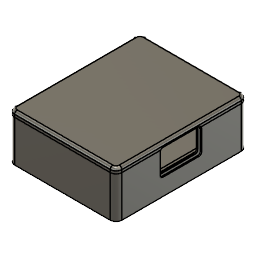
B_involucro_modulo_aquisicao (Autodesk Fusion 360 design; units mm, degrees)
Autodesk Fusion 360 part; units mm, degrees
sketch "Esboço1" plane through (0, 0, 0) normal (0, 0, 1) x (1, 0, 0)
  line L0 (0, 0) -> (38, 0)
  line L1 (0, 0) -> (0, 10)
  line L2 (0, 10) -> (4, 10)
  line L3 (4, 10) -> (4, 8)
  line L4 (4, 8) -> (2, 8)
  line L5 (2, 8) -> (2, 6)
  line L6 (2, 6) -> (4, 6)
  line L7 (4, 6) -> (4, 4)
  line L8 (4, 4) -> (2, 4)
  line L9 (2, 4) -> (2, 2)
  line L10 (2, 2) -> (38, 2)
  line L11 (38, 2) -> (38, 0)
  line L12 (38, 2) -> (38, 0)
  line L13 (38, 2) -> (38, 0)
  line L14 (76, 0) -> (38, 0)
  line L15 (72, 4) -> (74, 4)
  line L16 (74, 2) -> (38, 2)
  line L17 (76, 10) -> (72, 10)
  line L18 (72, 10) -> (72, 8)
  line L19 (74, 4) -> (74, 2)
  line L20 (74, 6) -> (72, 6)
  line L21 (38, 2) -> (38, 0)
  line L22 (72, 6) -> (72, 4)
  line L23 (72, 8) -> (74, 8)
  line L24 (74, 8) -> (74, 6)
  line L25 (76, 0) -> (76, 10)
  point P0 (76, 0)
  dimension "d2" = 10
  dimension "d3" = 4
  dimension "d4" = 2
  dimension "d5" = 2
  dimension "d6" = 2
  dimension "d7" = 2
  dimension "d8" = 2
  dimension "d9" = 2
  dimension "d10" = 2
  dimension "d11" = 36
  constraint coincident L0.start L1.start
  constraint horizontal L0
  constraint perpendicular L0 L1
  constraint perpendicular L1 L2
  constraint perpendicular L2 L3
  constraint perpendicular L1 L4
  constraint perpendicular L4 L5
  constraint perpendicular L5 L6
  constraint perpendicular L6 L7
  constraint perpendicular L7 L8
  constraint perpendicular L0 L9
  constraint perpendicular L9 L10
  constraint symmetric L10.end L11 L12.start
  constraint symmetric L0.end L11 L12.end
  constraint perpendicular L10 L12
  constraint symmetric L0.start L12 L14.start
  constraint symmetric L0.start L12 P0
  constraint symmetric L1.end L12 L17.start
  constraint symmetric L2.end L12 L17.end
  constraint symmetric L3.end L12 L18.end
  constraint symmetric L4.end L12 L23.end
  constraint symmetric L5.end L12 L20.start
  constraint symmetric L6.end L12 L20.end
  constraint symmetric L7.end L12 L15.start
  constraint symmetric L8.end L12 L15.end
  constraint symmetric L9.end L12 L16.start
  constraint symmetric L10.end L12 L11.start
  constraint symmetric L0.end L12 L11.end
  measures "d2" distance of L0.start L1.end
  measures "d3" distance of L1.end L2.end
  measures "d4" distance of L2.end L3.end
  measures "d5" distance of L3.end L4.end
  measures "d6" distance of L4.end L5.end
  measures "d7" distance of L5.end L6.end
  measures "d8" distance of L6.end L7.end
  measures "d9" distance of L7.end L8.end
  measures "d10" distance of L8.end L9.end
  measures "d11" distance of L9.end L10.end
extrude "Extrusão1" add sketch "Esboço1" along normal blind 95 makes body 1
fillet "Arredondamento1" radius 2 1 edges at (0, 10, 47.5) on bodies 1
fillet "Arredondamento1" radius 2 1 edges at (76, 10, 47.5) on bodies 1
sketch "Esboço3" plane through (0, 0, 95) normal (0, 0, 1) x (1, 0, 0)
  line L0 (74, 2) -> (2, 2)
  line L1 (2, 2) -> (2, 4)
  line L2 (2, 4) -> (4, 4)
  line L3 (4, 4) -> (4, 6)
  line L4 (4, 6) -> (2, 6)
  line L5 (2, 6) -> (2, 8)
  line L6 (2, 8) -> (4, 8)
  line L7 (4, 8) -> (4, 10)
  line L8 (4, 10) -> (2, 10)
  arc A0 (2, 10) -> (0, 8) centre (2, 8) ccw
  line L9 (0, 8) -> (0, 0)
  line L10 (0, 0) -> (76, 0)
  line L11 (2, 8) -> (4, 8)
  line L12 (4, 8) -> (4, 6)
  line L13 (4, 6) -> (2, 6)
  line L14 (2, 6) -> (2, 8)
  line L15 (72, 8) -> (74, 8)
  line L16 (74, 8) -> (74, 6)
  line L17 (74, 6) -> (72, 6)
  line L18 (72, 6) -> (72, 8)
  line L19 (76, 0) -> (76, 8)
  line L20 (74, 10) -> (72, 10)
  line L21 (72, 10) -> (72, 8)
  line L22 (72, 8) -> (74, 8)
  line L23 (74, 8) -> (74, 6)
  line L24 (74, 6) -> (72, 6)
  line L25 (72, 6) -> (72, 4)
  line L26 (72, 4) -> (74, 4)
  line L27 (74, 4) -> (74, 2)
  arc A1 (76, 8) -> (74, 10) centre (74, 8) ccw
  constraint horizontal L11
  constraint vertical L12
  constraint horizontal L13
  constraint vertical L14
  constraint coincident L3.end L4.start
  constraint coincident L5.end L6.start
  constraint horizontal L15
  constraint vertical L16
  constraint horizontal L17
  constraint vertical L18
  measures "d143" distance of L9.end
copy_body "Corpo -> Componente1" bodies 1 removing the originals makes body 2 in component "Placa 9x7"
extrude "Extrusão1'" add sketch "Esboço3" against normal blind 2 contours L15 L16 L17 L18 L22 L23 L24 | L4 L5 L6 L11 L12 L13 L14 bodies 2 in component "Placa 9x7"
sketch "Esboço7" plane through (0, 0, 0) normal (0, -1, 0) x (1, 0, 0)
  line L0 (0, 0) -> (76, 0)
  line L1 (76, 95) -> (0, 95)
  line L2 (0, 95) -> (0, 0)
  line L3 (0, 0) -> (0, 47.5)
  line L4 (0, 47.5) -> (38, 47.5)
  line L5 (77, -0.75) -> (-1, -0.75)
  line L6 (-1, -0.75) -> (-1, 95.75)
  line L7 (-1, 95.75) -> (77, 95.75)
  line L8 (77, 95.75) -> (77, -0.75)
  line L9 (77, -0.75) -> (-1, 95.75) construction
  line L10 (-1, -0.75) -> (77, 95.75) construction
  line L11 (75, 97.75) -> (1, 97.75)
  line L12 (-3, 93.75) -> (-3, 1.25)
  line L13 (1, -2.75) -> (75, -2.75)
  line L14 (79, 1.25) -> (79, 93.75)
  line L15 (79, 97.75) -> (-3, -2.75) construction
  line L16 (-3, 97.75) -> (79, -2.75) construction
  arc A0 (1, 97.75) -> (-3, 93.75) centre (1, 93.75) ccw
  arc A1 (79, 93.75) -> (75, 97.75) centre (75, 93.75) ccw
  arc A2 (75, -2.75) -> (79, 1.25) centre (75, 1.25) ccw
  arc A3 (-3, 1.25) -> (1, -2.75) centre (1, 1.25) ccw
  line L17 (76, 0) -> (76, 95)
  point P0 (38, 47.5)
  point P1 (38, 47.5)
  dimension "d45" = 47.5
  dimension "d46" = 38
  dimension "d47" = 96.5
  dimension "d48" = 78
  dimension "d49" = 82
  dimension "d50" = 100.5
  dimension "d54" = 4
  constraint coincident L0.start L2.end
  constraint perpendicular L0 L3
  constraint perpendicular L3 L4
  constraint horizontal L5
  constraint perpendicular L5 L6
  constraint parallel L5 L7
  constraint parallel L6 L8
  constraint coincident L9 P1
  constraint coincident L10 P1
  constraint coincident P1 P0
  constraint horizontal L11
  constraint perpendicular L11 L12
  constraint parallel L11 L13
  constraint parallel L12 L14
  constraint coincident L15 P1
  constraint coincident L16 P1
  constraint coincident L16.start L12
  constraint coincident L16.start L11
  constraint tangent L12 A0
  constraint tangent L11 A0
  constraint coincident L15.start L11
  constraint coincident L15.start L14
  constraint tangent L11 A1
  constraint tangent L14 A1
  constraint equal A0 A1
  constraint coincident L16.end L13
  constraint coincident L16.end L14
  constraint tangent L13 A2
  constraint tangent L14 A2
  constraint equal A0 A2
  constraint coincident L15.end L13
  constraint coincident L15.end L12
  constraint tangent L13 A3
  constraint tangent L12 A3
  constraint equal A0 A3
  measures "d45" distance of L0.start L3.end
  measures "d46" distance of L3.end P1
  measures "d47" distance of L5.end L6.end
  measures "d48" distance of L6.end L7.end
  measures "d49" distance of L15.end L16.end
  measures "d50" distance of L16.start L15.end
  measures "d54" radius of A0
extrude "Extrusão8" add sketch "Esboço7" against normal blind 30 thin wall 1 centred separate body contours L11 L12 L13 L14 A0 A1 A2 A3 makes body 3
copy_body "Corpo -> Componente2" bodies 3 removing the originals makes body 4 in component "Suporte Placa (1)"
extrude "Extrusão1''" add sketch "Esboço7" along normal blind 2 contours L0 L1 L2 L3 L17 | L5 L6 L7 L8 | L11 L12 L13 L14 A0 A1 A2 A3 bodies 4 in component "Suporte Placa (1)"
extrude "Extrusão11" add 1 faces at (51.6667, -2, 62.9167) along direction (0, 1, 0) blind 2 thin wall 0.5 outside on bodies 4 bodies 4 in component "Suporte Placa (1)"
sketch "Esboço1 (2)" plane through (0, 30, 0) normal (0, 1, 0) x (-1, 0, 0) in component "Suporte Placa (1)"
  arc A0 (2.5, 93.75) -> (1.5, 96.1995) centre (-1, 93.75) ccw
  line L0 (2.5, 93.75) -> (2.5, 1.25)
  arc A1 (1.5, -1.1995) -> (2.5, 1.25) centre (-1, 1.25) ccw
  line L1 (1.5, -1.1995) -> (1.5, 96.1995)
  arc A2 (-75, 97.25) -> (-77.4495, 96.25) centre (-75, 93.75) ccw
  line L2 (-75, 97.25) -> (-1, 97.25)
  arc A3 (1.4495, 96.25) -> (-1, 97.25) centre (-1, 93.75) ccw
  line L3 (1.4495, 96.25) -> (-77.4495, 96.25)
  arc A4 (-1, -2.25) -> (1.4495, -1.25) centre (-1, 1.25) ccw
  line L4 (-1, -2.25) -> (-75, -2.25)
  arc A5 (-77.4495, -1.25) -> (-75, -2.25) centre (-75, 1.25) ccw
  line L5 (-77.4495, -1.25) -> (1.4495, -1.25)
  arc A6 (-78.5, 1.25) -> (-77.5, -1.1995) centre (-75, 1.25) ccw
  line L6 (-78.5, 1.25) -> (-78.5, 93.75)
  arc A7 (-77.5, 96.1995) -> (-78.5, 93.75) centre (-75, 93.75) ccw
  line L7 (-77.5, 96.1995) -> (-77.5, -1.1995)
  line L8 (-76.5, 95.25) -> (0.5, 95.25)
  line L9 (0.5, 95.25) -> (0.5, -0.25)
  line L10 (0.5, -0.25) -> (-76.5, -0.25)
  line L11 (-76.5, -0.25) -> (-76.5, 95.25)
  arc A8 (-1, -3.25) -> (3.5, 1.25) centre (-1, 1.25) ccw
  line L12 (3.5, 1.25) -> (3.5, 93.75)
  arc A9 (3.5, 93.75) -> (-1, 98.25) centre (-1, 93.75) ccw
  line L13 (-1, 98.25) -> (-75, 98.25)
  arc A10 (-75, 98.25) -> (-79.5, 93.75) centre (-75, 93.75) ccw
  line L14 (-79.5, 93.75) -> (-79.5, 1.25)
  line L15 (-75, -3.25) -> (-1, -3.25)
  line L16 (0.5, -0.25) -> (0.5, 1.75)
  line L17 (0.5, -0.25) -> (-1.5, -0.25)
  line L18 (-1.5, -0.25) -> (-1.5, -3.25)
  line L19 (0.5, 1.75) -> (3.5, 1.75)
  line L20 (-42.25, -3.25) -> (-42.75, -3.25)
  line L21 (-47.25, 1.25) -> (-47.25, 1.75)
  line L22 (-38, -3.25) -> (-38, 32.5)
  line L23 (-38, 32.5) -> (3.5, 47.5)
  arc A11 (-26.0705, 83.0619) -> (-32.4078, 83.6448) centre (-29.5306, 80.1847) ccw
  line L24 (-30.8741, 81.0184) -> (-32.7922, 83.3251)
  line L25 (-29.3363, 82.2971) -> (-30.8741, 81.0184)
  line L26 (-28.0576, 80.7593) -> (-25.7509, 82.6774)
  line L27 (-28.0576, 80.7593) -> (0.5, 95.25)
  line L28 (-76.5, 1.75) -> (-79.5, 1.75)
  line L29 (-76.5, -0.25) -> (-76.5, 1.75)
  line L30 (-76.5, -0.25) -> (-74.5, -0.25)
  line L31 (-74.5, -0.25) -> (-74.5, -3.25)
  arc A12 (-79.5, 1.25) -> (-75, -3.25) centre (-75, 1.25) ccw
  line L32 (-47.9424, 80.7593) -> (-50.2491, 82.6774)
  line L33 (-47.9424, 80.7593) -> (-76.5, 95.25)
  line L34 (-46.6637, 82.2971) -> (-45.1259, 81.0184)
  line L35 (-45.1259, 81.0184) -> (-43.2078, 83.3251)
  arc A13 (-43.5922, 83.6448) -> (-49.9295, 83.0619) centre (-46.4694, 80.1847) ccw
  dimension "d57" = 2
  dimension "d58" = 2
  dimension "d59" = 35.75
  constraint coincident L9.end L10.start
  constraint perpendicular L10 L16
  constraint perpendicular L16 L17
  constraint coincident L15 L18.end
  constraint perpendicular L15 L18
  constraint coincident L12 L19.end
  constraint perpendicular L12 L19
  constraint midpoint L15 L22.start
  constraint perpendicular L10 L22
  constraint midpoint L12 L23.end
  constraint symmetric A8.start L23 A11.end
  constraint symmetric A8.end L23 A11.start
  constraint symmetric A8 L23 A11
  constraint symmetric L16.end L23 L26.start
  constraint symmetric L9.end L23 L25.start
  constraint symmetric L17.end L23 L24.start
  constraint symmetric L18.end L23 L24.end
  constraint symmetric L19.end L23 L26.end
  constraint coincident L8.end L9.start
  constraint symmetric A8.start L22 L15.start
  constraint symmetric A8.end L22 L14.end
  constraint symmetric A8 L22 A12
  constraint symmetric L9.end L22 L10.end
  constraint symmetric L16.end L22 L28.start
  constraint symmetric L17.end L22 L30.end
  constraint symmetric L18.end L22 L31.end
  constraint symmetric L19.end L22 L28.end
  constraint symmetric L22 A11.end A13.start
  constraint symmetric L22 A11.start A13.end
  constraint symmetric L22 A11 A13
  constraint symmetric L22 L24.start L34.end
  constraint symmetric L22 L24.end L35.end
  constraint symmetric L22 L25.start L34.start
  constraint symmetric L22 L26.start L32.start
  constraint symmetric L22 L26.end L32.end
  constraint symmetric L22 L8.end L8.start
  measures "d57" distance of L9.end L16.end
  measures "d58" distance of L9.end L17.end
  measures "d59" distance of L22.start L22.end
ref_plane "Plano de trabalho1" through (38, 30, 47.5) normal (0, 1, 0) x (-1, 0, 0) in component "Suporte Placa (1)"
sketch "Esboço3 (2)" plane through (0, 30, 0) normal (0, 1, 0) x (1, 0, 0) in component "Suporte Placa (1)"
extrude "Extrusão7" add 1 faces at (-1.1667, 30, 31.5833) along direction (0, 1, 0) blind 2 separate body on bodies 4 makes body 5 in component "Suporte Placa (1)"
copy_body "CutPasteBodies1" bodies 5 removing the originals makes body 6 in component "Tampa"
sketch "Esboço1 (3)" plane through (0, 32, 0) normal (0, 1, 0) x (-1, 0, 0) in component "Tampa"
  line L0 (-76.5, -0.25) -> (-76.5, 95.25)
  line L1 (-76.5, 95.25) -> (0.5, 95.25)
  line L2 (0.5, 95.25) -> (0.5, -0.25)
  line L3 (0.5, -0.25) -> (-76.5, -0.25)
  line L4 (-77.5, 96.1995) -> (-77.5, -1.1995)
  line L5 (-78.5, 1.25) -> (-78.5, 93.75)
  line L6 (-79.5, 93.75) -> (-79.5, 1.25)
  arc A0 (-79.5, 1.25) -> (-75, -3.25) centre (-75, 1.25) ccw
  line L7 (-75, -3.25) -> (-1, -3.25)
  arc A1 (-1, -3.25) -> (3.5, 1.25) centre (-1, 1.25) ccw
  line L8 (3.5, 1.25) -> (3.5, 93.75)
  arc A2 (3.5, 93.75) -> (-1, 98.25) centre (-1, 93.75) ccw
  line L9 (-1, 98.25) -> (-75, 98.25)
  arc A3 (-75, 98.25) -> (-79.5, 93.75) centre (-75, 93.75) ccw
  line L10 (2.5, 93.75) -> (2.5, 1.25)
  line L11 (1.5, -1.1995) -> (1.5, 96.1995)
  line L12 (-75, 97.25) -> (-1, 97.25)
  line L13 (1.4495, 96.25) -> (-77.4495, 96.25)
  line L14 (-1, -2.25) -> (-75, -2.25)
  line L15 (-77.4495, -1.25) -> (1.4495, -1.25)
  arc A4 (2.5, 93.75) -> (1.5, 96.1995) centre (-1, 93.75) ccw
  arc A5 (1.5, -1.1995) -> (2.5, 1.25) centre (-1, 1.25) ccw
  arc A6 (-75, 97.25) -> (-77.4495, 96.25) centre (-75, 93.75) ccw
  arc A7 (1.4495, 96.25) -> (-1, 97.25) centre (-1, 93.75) ccw
  arc A8 (-1, -2.25) -> (1.4495, -1.25) centre (-1, 1.25) ccw
  arc A9 (-77.4495, -1.25) -> (-75, -2.25) centre (-75, 1.25) ccw
  arc A10 (-78.5, 1.25) -> (-77.5, -1.1995) centre (-75, 1.25) ccw
  arc A11 (-77.5, 96.1995) -> (-78.5, 93.75) centre (-75, 93.75) ccw
extrude "Extrusão1'''" add sketch "Esboço1 (3)" along normal blind 2 contours L0 L1 L2 L3 | L4 L5 A10 A11 | L6 A0 L7 A1 L8 A2 L9 A3 | L10 L11 A4 A5 | L12 L13 A6 A7 | L14 L15 A8 A9 bodies 6 in component "Tampa"
extrude "Extrusão6" add sketch "Esboço1 (3)" along normal blind 2 and the other way blind 4 contours L4 L5 A10 A11 | L10 L11 A4 A5 | L12 L13 A6 A7 | L14 L15 A8 A9 bodies 6 in component "Tampa"
fillet "Arredondamento1'" radius 2 8 edges at (79.5, 34, 47.5) (78.182, 34, -1.932) (38, 34, -3.25) (-2.182, 34, -1.932) (-3.5, 34, 47.5) (-2.182, 34, 96.932) (38, 34, 98.25) (78.182, 34, 96.932) on bodies 6 in component "Tampa"
sketch "Esboço8" plane through (79.5, 0, 0) normal (1, 0, 0) x (0, 0, -1)
  line L0 (-1.25, -2) -> (-1.25, 30)
  line L1 (-1.25, 30) -> (-93.75, 30)
  line L2 (-93.75, 30) -> (-93.75, -2)
  line L3 (-93.75, -2) -> (-48, -2)
  line L4 (-48, -2) -> (-48, 21)
  line L5 (-34, 31) -> (-62, 31)
  line L6 (-64, 29) -> (-64, 13)
  line L7 (-62, 11) -> (-34, 11)
  line L8 (-32, 13) -> (-32, 29)
  line L9 (-32, 31) -> (-64, 11) construction
  line L10 (-64, 31) -> (-32, 11) construction
  arc A0 (-62, 31) -> (-64, 29) centre (-62, 29) ccw
  arc A1 (-64, 13) -> (-62, 11) centre (-62, 13) ccw
  arc A2 (-34, 11) -> (-32, 13) centre (-34, 13) ccw
  arc A3 (-32, 29) -> (-34, 31) centre (-34, 29) ccw
  line L11 (-35, 30) -> (-61, 30)
  line L12 (-63, 28) -> (-63, 14)
  line L13 (-61, 12) -> (-35, 12)
  line L14 (-33, 14) -> (-33, 28)
  line L15 (-33, 30) -> (-63, 12) construction
  line L16 (-63, 30) -> (-33, 12) construction
  arc A4 (-61, 30) -> (-63, 28) centre (-61, 28) ccw
  arc A5 (-63, 14) -> (-61, 12) centre (-61, 14) ccw
  arc A6 (-35, 12) -> (-33, 14) centre (-35, 14) ccw
  arc A7 (-33, 28) -> (-35, 30) centre (-35, 28) ccw
  line L17 (-93.75, -2) -> (-1.25, -2)
  line L18 (-93.75, -2) -> (-48, -2)
  point P0 (-48, 21)
  point P1 (-48, 21)
  dimension "d99" = 23
  dimension "d100" = 32
  dimension "d101" = 20
  dimension "d102" = 2
  dimension "d103" = 30
  dimension "d104" = 18
  dimension "d105" = 2
  dimension "d143" = 45.75
  constraint coincident L2.end L3.start
  constraint horizontal L5
  constraint perpendicular L5 L6
  constraint parallel L5 L7
  constraint parallel L6 L8
  constraint coincident L9 P1
  constraint coincident L10 P1
  constraint coincident P1 P0
  constraint coincident L10.start L5
  constraint coincident L10.start L6
  constraint tangent L5 A0
  constraint tangent L6 A0
  constraint coincident L9.end L6
  constraint coincident L9.end L7
  constraint tangent L6 A1
  constraint tangent L7 A1
  constraint equal A0 A1
  constraint coincident L10.end L8
  constraint coincident L10.end L7
  constraint tangent L8 A2
  constraint tangent L7 A2
  constraint equal A0 A2
  constraint coincident L9.start L8
  constraint coincident L9.start L5
  constraint tangent L8 A3
  constraint tangent L5 A3
  constraint equal A0 A3
  constraint horizontal L11
  constraint perpendicular L11 L12
  constraint parallel L11 L13
  constraint parallel L12 L14
  constraint coincident L15 P1
  constraint coincident L16 P1
  constraint coincident L16.start L11
  constraint coincident L16.start L12
  constraint tangent L11 A4
  constraint tangent L12 A4
  constraint coincident L15.end L12
  constraint coincident L15.end L13
  constraint tangent L12 A5
  constraint tangent L13 A5
  constraint equal A4 A5
  constraint coincident L16.end L13
  constraint coincident L16.end L14
  constraint tangent L13 A6
  constraint tangent L14 A6
  constraint equal A4 A6
  constraint coincident L15.start L14
  constraint coincident L15.start L11
  constraint tangent L14 A7
  constraint tangent L11 A7
  constraint equal A4 A7
  constraint perpendicular L4 L18
  constraint perpendicular L2 L3
  measures "d100" distance of L9.end L10.end
  measures "d101" distance of L10.start L9.end
  measures "d102" radius of A0
  measures "d103" distance of L15.end L16.end
  measures "d104" distance of L16.start L15.end
  measures "d105" radius of A4
  measures "d143" distance of L2.end L3.end
extrude "Extrusão9" cut sketch "Esboço8" against normal blind 3 contours L1 L11 L12 L13 L14 A4 A5 A6 A7 bodies 4 in component "Suporte Placa (1)"
extrude "Extrusão4" [no effect] in component "Tampa"
extrude "Extrusão10" cut sketch "Esboço8" against normal blind 2 contours L1 L4 L7 L8 A2 A3 L13 L14 A6 A7 | L1 L5 A0 A3 L11 | L1 L4 L6 L7 A0 A1 L12 L13 A4 A5 | L1 L11 L12 L13 L14 A4 A5 A6 A7 bodies 4 in component "Suporte Placa (1)"
extrude "Extrusão5" cut sketch "Esboço8" against normal blind 2 contours L1 L4 L7 L8 A2 A3 L13 L14 A6 A7 | L1 L5 A0 A3 L11 | L1 L4 L6 L7 A0 A1 L12 L13 A4 A5 | L1 L11 L12 L13 L14 A4 A5 A6 A7 bodies 6 in component "Tampa"
sketch "Esboço12" plane through (0, 0, -3.25) normal (0, 0, -1) x (-1, 0, 0)
  line L0 (-1, -2) -> (-1, 30)
  line L1 (-1, 30) -> (-75, 30)
  line L2 (-75, 30) -> (-75, -2)
  line L3 (-75, -2) -> (-1, -2)
  line L4 (-75, -2) -> (-38, -2)
  line L5 (-38, -2) -> (-38, 18)
  line L6 (-5, 6) -> (-71, 6)
  line L7 (-73, 8) -> (-73, 28)
  line L8 (-71, 30) -> (-5, 30)
  line L9 (-3, 28) -> (-3, 8)
  line L10 (-3, 6) -> (-73, 30) construction
  line L11 (-73, 6) -> (-3, 30) construction
  line L12 (-4, 31) -> (-72, 31)
  line L13 (-74, 29) -> (-74, 7)
  line L14 (-72, 5) -> (-4, 5)
  line L15 (-2, 7) -> (-2, 29)
  line L16 (-2, 31) -> (-74, 5) construction
  line L17 (-74, 31) -> (-2, 5) construction
  arc A0 (-72, 31) -> (-74, 29) centre (-72, 29) ccw
  arc A1 (-71, 30) -> (-73, 28) centre (-71, 28) ccw
  arc A2 (-73, 8) -> (-71, 6) centre (-71, 8) ccw
  arc A3 (-74, 7) -> (-72, 5) centre (-72, 7) ccw
  arc A4 (-5, 6) -> (-3, 8) centre (-5, 8) ccw
  arc A5 (-3, 28) -> (-5, 30) centre (-5, 28) ccw
  arc A6 (-2, 29) -> (-4, 31) centre (-4, 29) ccw
  arc A7 (-4, 5) -> (-2, 7) centre (-4, 7) ccw
  point P0 (-38, 18)
  point P1 (-38, 18)
  dimension "d144" = 20
  dimension "d145" = 70
  dimension "d146" = 24
  dimension "d147" = 72
  dimension "d148" = 26
  dimension "d153" = 2
  dimension "d154" = 2
  constraint coincident L2.end L3.start
  constraint midpoint L3 L4.end
  constraint perpendicular L3 L5
  constraint horizontal L6
  constraint perpendicular L6 L7
  constraint parallel L6 L8
  constraint parallel L7 L9
  constraint coincident L10 P1
  constraint coincident L11 P1
  constraint coincident P1 P0
  constraint horizontal L12
  constraint perpendicular L12 L13
  constraint parallel L12 L14
  constraint parallel L13 L15
  constraint coincident L16 P1
  constraint coincident L17 P1
  constraint coincident L17.start L13
  constraint coincident L17.start L12
  constraint tangent L13 A0
  constraint tangent L12 A0
  constraint coincident L10.end L7
  constraint coincident L10.end L8
  constraint tangent L7 A1
  constraint tangent L8 A1
  constraint coincident L11.start L7
  constraint coincident L11.start L6
  constraint tangent L7 A2
  constraint tangent L6 A2
  constraint equal A1 A2
  constraint coincident L16.end L13
  constraint coincident L16.end L14
  constraint tangent L13 A3
  constraint tangent L14 A3
  constraint equal A1 A3
  constraint coincident L10.start L6
  constraint coincident L10.start L9
  constraint tangent L6 A4
  constraint tangent L9 A4
  constraint equal A1 A4
  constraint coincident L11.end L8
  constraint coincident L11.end L9
  constraint tangent L8 A5
  constraint tangent L9 A5
  constraint equal A1 A5
  constraint coincident L16.start L12
  constraint coincident L16.start L15
  constraint tangent L12 A6
  constraint tangent L15 A6
  constraint equal A1 A6
  constraint coincident L17.end L15
  constraint coincident L17.end L14
  constraint tangent L15 A7
  constraint tangent L14 A7
  constraint equal A1 A7
  measures "d144" distance of L4.end P1
  measures "d145" distance of L10.end L11.end
  measures "d146" distance of L11.start L10.end
  measures "d147" distance of L16.end L17.end
  measures "d148" distance of L17.start L16.end
  measures "d153" radius of A0
  measures "d154" radius of A1
extrude "Extrusão12" cut sketch "Esboço12" against normal blind 3 contours L1 L6 L7 L8 L9 A1 A2 A4 A5 bodies 4 in component "Suporte Placa (1)"
extrude "Extrusão11'" cut sketch "Esboço12" against normal blind 3 contours L1 L6 L7 L8 L9 A1 A2 A4 A5 bodies 6 in component "Tampa"
extrude "Extrusão13" cut sketch "Esboço12" against normal blind 2 contours L1 L5 L6 L9 L14 L15 A4 A5 A6 A7 | L1 L5 L6 L7 L13 L14 A0 A1 A2 A3 bodies 4 in component "Suporte Placa (1)"
sketch "Esboço11" plane through (0, 34, 0) normal (0, 1, 0) x (-1, 0, 0)
  line L0 (-77.5, 93.75) -> (-77.5, 1.25)
  arc A0 (-77.5, 1.25) -> (-75, -1.25) centre (-75, 1.25) ccw
  line L1 (-75, -1.25) -> (-1, -1.25)
  arc A1 (-1, -1.25) -> (1.5, 1.25) centre (-1, 1.25) ccw
  line L2 (1.5, 1.25) -> (1.5, 93.75)
  arc A2 (1.5, 93.75) -> (-1, 96.25) centre (-1, 93.75) ccw
  line L3 (-1, 96.25) -> (-75, 96.25)
  arc A3 (-75, 96.25) -> (-77.5, 93.75) centre (-75, 93.75) ccw
  spline S0 degree 3 poles (-69.7315, 86.0549) (-70.316, 86.6737) (-71.5537, 86.7631) (-71.9181, 86.2061) knots 0 0 0 0 1 1 1 1
  line L4 (-66.2728, 89.431) -> (-68.4044, 89.8986)
  line L5 (-72.2206, 83.9645) -> (-72.2206, 82.6856)
  spline S1 degree 3 poles (-70.3228, 84.9066) (-70.0959, 84.6796) (-70.089, 84.659) (-70.089, 84.1227) knots 0 0 0 0 1 1 1 1
  spline S2 degree 3 poles (-69.2914, 70.5012) (-70.3022, 71.0513) (-71.6637, 71.0375) (-72.7226, 70.4806) knots 0 0 0 0 1 1 1 1
  spline S3 degree 3 poles (-67.8062, 88.544) (-67.5862, 88.4959) (-66.3003, 88.2346) (-66.266, 88.2346) knots 0 0 0 0 1 1 1 1
  spline S4 degree 3 poles (-69.5527, 69.2154) (-69.9378, 69.5454) (-70.4191, 69.7036) (-71.0517, 69.6967) knots 0 0 0 0 1 1 1 1
  spline S5 degree 3 poles (-67.8062, 83.0706) (-67.9437, 83.105) (-68.315, 83.1875) (-68.6244, 83.2494) knots 0 0 0 0 1 1 1 1
  spline S6 degree 3 poles (-68.9682, 80.0383) (-69.037, 80.0039) (-69.6834, 79.8458) (-70.3985, 79.6739) knots 0 0 0 0 1 1 1 1
  spline S7 degree 3 poles (-71.258, 76.669) (-71.7118, 76.6346) (-71.8837, 76.5246) (-72.0831, 76.1327) knots 0 0 0 0 1 1 1 1
  line L6 (-70.3435, 89.1078) -> (-70.5085, 88.9634)
  spline S8 degree 3 poles (-68.7276, 76.1602) (-68.872, 76.2221) (-69.0026, 76.2702) (-69.0233, 76.2702) knots 0 0 0 0 1 1 1 1
  spline S9 degree 3 poles (-70.5085, 88.9634) (-70.9279, 88.599) (-71.0242, 88.1246) (-70.7973, 87.4988) knots 0 0 0 0 1 1 1 1
  spline S10 degree 3 poles (-71.0517, 69.6967) (-71.6843, 69.6967) (-72.0762, 69.5385) (-72.5644, 69.0778) knots 0 0 0 0 1 1 1 1
  line L7 (-70.089, 84.1227) -> (-70.089, 83.5726)
  spline S11 degree 3 poles (-71.3474, 72.4746) (-70.7629, 72.0345) (-70.2678, 71.8626) (-69.4633, 71.8214) knots 0 0 0 0 1 1 1 1
  spline S12 degree 3 poles (-73.3552, 68.4865) (-72.6951, 69.9373) (-70.8592, 70.453) (-69.539, 69.566) knots 0 0 0 0 1 1 1 1
  line L8 (-66.2522, 88.8328) -> (-66.2728, 89.431)
  line L9 (-70.8454, 76.6965) -> (-71.258, 76.669)
  spline S13 degree 3 poles (-70.8729, 78.3743) (-70.7629, 78.4018) (-69.979, 78.6012) (-69.1264, 78.8144) knots 0 0 0 0 1 1 1 1
  spline S14 degree 3 poles (-67.6343, 81.7161) (-67.5655, 81.6954) (-67.5449, 81.8467) (-67.5449, 82.3487) knots 0 0 0 0 1 1 1 1
  spline S15 degree 3 poles (-68.4044, 89.8986) (-69.5802, 90.153) (-70.591, 90.3593) (-70.6598, 90.3662) knots 0 0 0 0 1 1 1 1
  spline S16 degree 3 poles (-66.1009, 70.6112) (-66.1009, 70.8519) (-66.1216, 71.0444) (-66.1559, 71.0444) knots 0 0 0 0 1 1 1 1
  spline S17 degree 3 poles (-66.1559, 71.0444) (-66.1834, 71.0444) (-66.8229, 70.8794) (-67.5724, 70.68) knots 0 0 0 0 1 1 1 1
  spline S18 degree 3 poles (-70.2266, 64.7184) (-69.8278, 64.5671) (-69.484, 64.4434) (-69.4564, 64.4434) knots 0 0 0 0 1 1 1 1
  spline S19 degree 3 poles (-70.1853, 66.9256) (-69.9309, 67.4207) (-70.1716, 68.0395) (-70.6941, 68.2252) knots 0 0 0 0 1 1 1 1
  line L10 (-68.1294, 68.0464) -> (-68.15, 66.8981)
  spline S20 degree 3 poles (-71.4643, 63.8245) (-70.9967, 63.7282) (-70.4329, 63.5288) (-69.5527, 63.1438) knots 0 0 0 0 1 1 1 1
  line L11 (-66.0322, 69.4766) -> (-66.0322, 69.9305)
  spline S21 degree 3 poles (-69.4633, 71.8214) (-68.0744, 71.7389) (-67.538, 72.1927) (-67.428, 73.506) knots 0 0 0 0 1 1 1 1
  spline S22 degree 3 poles (-74.084, 69.1053) (-74.476, 68.3421) (-74.6066, 67.5445) (-74.4897, 66.7468) knots 0 0 0 0 1 1 1 1
  spline S23 degree 3 poles (-70.034, 65.6673) (-70.0547, 65.6123) (-70.2128, 65.6398) (-70.5635, 65.7704) knots 0 0 0 0 1 1 1 1
  line L12 (-66.5135, 68.5071) -> (-66.9604, 68.3834)
  spline S24 degree 3 poles (-69.2158, 63.9827) (-70.6254, 64.5671) (-71.0311, 64.7184) (-71.4299, 64.7872) knots 0 0 0 0 1 1 1 1
  spline S25 degree 3 poles (-73.3002, 67.4757) (-73.3139, 67.1663) (-73.2795, 66.8431) (-73.2314, 66.6781) knots 0 0 0 0 1 1 1 1
  line L13 (-66.1009, 70.178) -> (-66.1009, 70.6112)
  spline S26 degree 3 poles (-69.539, 69.566) (-69.3396, 69.4354) (-69.1608, 69.3254) (-69.1333, 69.3254) knots 0 0 0 0 1 1 1 1
  spline S27 degree 3 poles (-70.5635, 65.7704) (-70.8385, 65.8736) (-71.1205, 65.9561) (-71.1961, 65.9561) knots 0 0 0 0 1 1 1 1
  line L14 (-67.5724, 70.68) -> (-68.9407, 70.3087)
  line L15 (-67.9781, 69.3529) -> (-69.2708, 68.9747)
  spline S28 degree 3 poles (-66.3622, 69.8342) (-66.541, 69.7792) (-67.2699, 69.566) (-67.9781, 69.3529) knots 0 0 0 0 1 1 1 1
  line L16 (-68.9407, 70.3087) -> (-69.2914, 70.5012)
  line L17 (-67.2699, 64.8559) -> (-67.2699, 66.5818)
  spline S29 degree 3 poles (-67.4005, 68.2596) (-67.4693, 68.239) (-67.6618, 68.1839) (-67.8268, 68.1358) knots 0 0 0 0 1 1 1 1
  spline S30 degree 3 poles (-73.2314, 66.6781) (-73.0733, 66.2174) (-72.9357, 66.0042) (-72.5713, 65.6604) knots 0 0 0 0 1 1 1 1
  spline S31 degree 3 poles (-72.5713, 65.6604) (-72.1725, 65.2822) (-71.9456, 65.1722) (-71.3611, 65.0691) knots 0 0 0 0 1 1 1 1
  spline S32 degree 3 poles (-68.37, 73.9048) (-68.37, 73.2997) (-68.8032, 73.0935) (-69.759, 73.231) knots 0 0 0 0 1 1 1 1
  line L18 (-69.6834, 67.9914) -> (-67.8543, 68.5071)
  line L19 (-66.9811, 66.4787) -> (-66.9948, 64.5809)
  line L20 (-69.3189, 64.8559) -> (-68.2944, 64.8559)
  line L21 (-69.3671, 64.6496) -> (-69.3189, 64.8559)
  spline S33 degree 3 poles (-68.8582, 74.7919) (-68.5694, 74.6475) (-68.37, 74.283) (-68.37, 73.9048) knots 0 0 0 0 1 1 1 1
  spline S34 degree 3 poles (-72.0831, 76.1327) (-72.365, 75.5826) (-72.4407, 74.5099) (-72.2481, 73.7948) knots 0 0 0 0 1 1 1 1
  spline S35 degree 3 poles (-67.428, 73.506) (-67.3386, 74.6543) (-67.9093, 75.8233) (-68.7276, 76.1602) knots 0 0 0 0 1 1 1 1
  spline S36 degree 3 poles (-69.759, 73.231) (-70.9761, 73.4098) (-71.6912, 74.0424) (-71.5055, 74.7919) knots 0 0 0 0 1 1 1 1
  spline S37 degree 3 poles (-70.3985, 79.6739) (-71.1205, 79.502) (-71.8218, 79.3301) (-71.9662, 79.2888) knots 0 0 0 0 1 1 1 1
  line L22 (-70.7767, 89.1972) -> (-70.5566, 89.1491)
  spline S38 degree 3 poles (-71.1273, 68.7615) (-70.5154, 68.8028) (-70.1234, 68.6309) (-69.7865, 68.1496) knots 0 0 0 0 1 1 1 1
  line L23 (-69.7865, 68.1496) -> (-69.6834, 67.9914)
  line L24 (-67.5449, 82.3487) -> (-67.5449, 83.0019)
  line L25 (-67.5793, 79.1994) -> (-67.5587, 80.1277)
  spline S39 degree 3 poles (-66.266, 88.2346) (-66.2453, 88.2346) (-66.2453, 88.5027) (-66.2522, 88.8328) knots 0 0 0 0 1 1 1 1
  line L26 (-69.1814, 83.3663) -> (-69.2089, 84.274)
  spline S40 degree 3 poles (-71.1067, 83.7995) (-71.2442, 83.8339) (-71.258, 83.8751) (-71.258, 84.3496) knots 0 0 0 0 1 1 1 1
  spline S41 degree 3 poles (-72.2481, 73.7948) (-72.1037, 73.2447) (-71.8287, 72.839) (-71.3474, 72.4746) knots 0 0 0 0 1 1 1 1
  line L27 (-67.5449, 83.0019) -> (-67.8062, 83.0706)
  spline S42 degree 3 poles (-67.6343, 76.4077) (-67.5655, 76.4077) (-67.5449, 76.5521) (-67.5449, 76.9922) knots 0 0 0 0 1 1 1 1
  spline S43 degree 3 poles (-71.0379, 78.2918) (-71.0517, 78.3124) (-70.9761, 78.3468) (-70.8729, 78.3743) knots 0 0 0 0 1 1 1 1
  spline S44 degree 3 poles (-67.5449, 76.9922) (-67.5449, 77.3154) (-67.5518, 77.5767) (-67.5655, 77.5767) knots 0 0 0 0 1 1 1 1
  line L28 (-70.7767, 89.7817) -> (-70.7767, 89.1972)
  spline S45 degree 3 poles (-70.6941, 68.2252) (-70.9486, 68.3146) (-71.0173, 68.3146) (-71.2717, 68.2252) knots 0 0 0 0 1 1 1 1
  spline S46 degree 3 poles (-72.1381, 77.336) (-71.9937, 77.2879) (-67.7374, 76.4077) (-67.6343, 76.4077) knots 0 0 0 0 1 1 1 1
  spline S47 degree 3 poles (-72.7226, 70.4806) (-73.1695, 70.2399) (-73.864, 69.5385) (-74.084, 69.1053) knots 0 0 0 0 1 1 1 1
  spline S48 degree 3 poles (-67.7237, 88.2758) (-67.9437, 88.5577) (-67.9506, 88.5784) (-67.8062, 88.544) knots 0 0 0 0 1 1 1 1
  line L29 (-66.0322, 69.0159) -> (-66.0322, 69.4766)
  line L30 (-66.0322, 69.9305) -> (-66.3622, 69.8342)
  line L31 (-71.9662, 79.2888) -> (-72.2206, 79.22)
  line L32 (-69.1264, 78.8144) -> (-67.5793, 79.1994)
  spline S49 degree 3 poles (-70.5154, 80.4715) (-69.3946, 80.2171) (-68.8789, 80.0727) (-68.9682, 80.0383) knots 0 0 0 0 1 1 1 1
  line L33 (-67.8268, 68.1358) -> (-68.1294, 68.0464)
  line L34 (-72.1863, 80.8497) -> (-70.5154, 80.4715)
  line L35 (-67.5449, 81.0491) -> (-69.759, 81.5235)
  line L36 (-67.5999, 69.7517) -> (-66.1009, 70.178)
  line L37 (-72.2206, 79.22) -> (-72.2206, 78.2918)
  spline S50 degree 3 poles (-66.0665, 68.6378) (-66.0665, 68.6309) (-66.266, 68.5759) (-66.5135, 68.5071) knots 0 0 0 0 1 1 1 1
  line L38 (-70.089, 83.5726) -> (-70.5222, 83.6689)
  line L39 (-69.0576, 75.5826) -> (-69.0576, 74.9019)
  line L40 (-70.8454, 75.9677) -> (-70.8454, 76.6965)
  spline S51 degree 3 poles (-69.1333, 69.3254) (-69.1126, 69.3254) (-68.4182, 69.5179) (-67.5999, 69.7517) knots 0 0 0 0 1 1 1 1
  spline S52 degree 3 poles (-69.9722, 82.218) (-68.7276, 81.9636) (-67.6755, 81.7367) (-67.6343, 81.7161) knots 0 0 0 0 1 1 1 1
  spline S53 degree 3 poles (-69.0233, 76.2702) (-69.0439, 76.2702) (-69.0576, 75.9608) (-69.0576, 75.5826) knots 0 0 0 0 1 1 1 1
  line L41 (-72.2069, 81.4548) -> (-72.1863, 80.8497)
  spline S54 degree 3 poles (-71.1205, 85.0028) (-70.9073, 85.216) (-70.5979, 85.1816) (-70.3228, 84.9066) knots 0 0 0 0 1 1 1 1
  line L42 (-70.8454, 75.2388) -> (-70.8454, 75.9677)
  spline S55 degree 3 poles (-70.6598, 90.3662) (-70.7629, 90.3662) (-70.7767, 90.2905) (-70.7767, 89.7817) knots 0 0 0 0 1 1 1 1
  spline S56 degree 3 poles (-69.6834, 86.5018) (-69.3946, 86.3918) (-69.1539, 86.3505) (-68.707, 86.3437) knots 0 0 0 0 1 1 1 1
  spline S57 degree 3 poles (-70.7973, 87.4988) (-70.6666, 87.1275) (-70.1991, 86.7081) (-69.6834, 86.5018) knots 0 0 0 0 1 1 1 1
  line L43 (-69.2708, 68.9747) -> (-69.5527, 69.2154)
  line L44 (-68.6244, 83.2494) -> (-69.1814, 83.3663)
  spline S58 degree 3 poles (-69.2089, 84.274) (-69.2364, 85.2572) (-69.3533, 85.656) (-69.7315, 86.0549) knots 0 0 0 0 1 1 1 1
  spline S59 degree 3 poles (-67.2699, 66.5818) (-67.2699, 68.2321) (-67.2767, 68.3008) (-67.4005, 68.2596) knots 0 0 0 0 1 1 1 1
  spline S60 degree 3 poles (-67.8406, 86.5293) (-67.6205, 86.6737) (-67.5449, 86.7768) (-67.483, 87.0313) knots 0 0 0 0 1 1 1 1
  line L45 (-71.0173, 75.2388) -> (-70.8454, 75.2388)
  line L46 (-72.2206, 82.6856) -> (-69.9722, 82.218)
  spline S61 degree 3 poles (-68.707, 86.3437) (-68.1844, 86.3437) (-68.0881, 86.3643) (-67.8406, 86.5293) knots 0 0 0 0 1 1 1 1
  spline S62 degree 3 poles (-70.5222, 83.6689) (-70.756, 83.7239) (-71.0173, 83.7789) (-71.1067, 83.7995) knots 0 0 0 0 1 1 1 1
  spline S63 degree 3 poles (-67.483, 87.0313) (-67.3661, 87.492) (-67.4486, 87.9114) (-67.7237, 88.2758) knots 0 0 0 0 1 1 1 1
  spline S64 degree 3 poles (-71.3611, 65.0691) (-71.1342, 65.0278) (-70.6254, 64.8697) (-70.2266, 64.7184) knots 0 0 0 0 1 1 1 1
  line L47 (-68.3013, 62.6006) -> (-68.3013, 63.1438)
  line L48 (-68.0606, 64.5809) -> (-69.1264, 64.5809)
  line L49 (-68.15, 66.8981) -> (-68.1637, 65.7498)
  line L50 (-68.1637, 65.7498) -> (-69.0851, 65.7498)
  line L51 (-66.9948, 64.5809) -> (-68.0606, 64.5809)
  spline S65 degree 3 poles (-71.7462, 66.8775) (-71.4093, 66.3205) (-70.4879, 66.348) (-70.1853, 66.9256) knots 0 0 0 0 1 1 1 1
  line L52 (-67.2011, 63.687) -> (-66.1009, 63.687)
  line L53 (-66.1009, 63.687) -> (-66.0872, 66.1624)
  line L54 (-68.2944, 64.8559) -> (-67.2699, 64.8559)
  line L55 (-69.1264, 64.5809) -> (-69.1264, 64.2646)
  spline S66 degree 3 poles (-74.1459, 65.7773) (-73.6233, 64.7115) (-72.7707, 64.0927) (-71.4643, 63.8245) knots 0 0 0 0 1 1 1 1
  spline S67 degree 3 poles (-69.0851, 65.7498) (-69.7384, 65.7498) (-70.0203, 65.7223) (-70.034, 65.6673) knots 0 0 0 0 1 1 1 1
  line L56 (-68.3013, 63.1438) -> (-68.3013, 63.687)
  spline S68 degree 3 poles (-69.4564, 64.4434) (-69.4358, 64.4434) (-69.3946, 64.5396) (-69.3671, 64.6496) knots 0 0 0 0 1 1 1 1
  spline S69 degree 3 poles (-71.1961, 65.9561) (-71.3955, 65.9561) (-71.8149, 66.1899) (-72.0281, 66.4168) knots 0 0 0 0 1 1 1 1
  spline S70 degree 3 poles (-74.4897, 66.7468) (-74.4485, 66.5131) (-74.3041, 66.0936) (-74.1459, 65.7773) knots 0 0 0 0 1 1 1 1
  line L57 (-69.5527, 63.1438) -> (-68.3013, 62.6006)
  spline S71 degree 3 poles (-69.1264, 64.2646) (-69.1264, 64.0377) (-69.1539, 63.9552) (-69.2158, 63.9827) knots 0 0 0 0 1 1 1 1
  line L58 (-68.3013, 63.687) -> (-67.2011, 63.687)
  spline S72 degree 3 poles (-71.258, 84.3496) (-71.258, 84.7759) (-71.2305, 84.8928) (-71.1205, 85.0028) knots 0 0 0 0 1 1 1 1
  spline S73 degree 3 poles (-71.4299, 64.7872) (-73.197, 65.0828) (-74.1116, 66.8362) (-73.3552, 68.4865) knots 0 0 0 0 1 1 1 1
  spline S74 degree 3 poles (-71.9181, 86.2061) (-72.1381, 85.8623) (-72.2206, 85.2916) (-72.2206, 83.9645) knots 0 0 0 0 1 1 1 1
  spline S75 degree 3 poles (-72.5644, 69.0778) (-73.0458, 68.6309) (-73.2727, 68.1427) (-73.3002, 67.4757) knots 0 0 0 0 1 1 1 1
  spline S76 degree 3 poles (-72.0281, 66.4168) (-72.8532, 67.2832) (-72.3169, 68.6721) (-71.1273, 68.7615) knots 0 0 0 0 1 1 1 1
  spline S77 degree 3 poles (-71.2717, 68.2252) (-71.8149, 68.0327) (-72.0487, 67.3726) (-71.7462, 66.8775) knots 0 0 0 0 1 1 1 1
  line L59 (-66.9604, 68.3834) -> (-66.9811, 66.4787)
  spline S78 degree 3 poles (-68.1637, 88.042) (-68.1637, 87.8151) (-68.2188, 87.7326) (-68.425, 87.6226) knots 0 0 0 0 1 1 1 1
  spline S79 degree 3 poles (-70.0547, 88.0558) (-70.1991, 88.2552) (-70.1853, 88.6059) (-70.0272, 88.7434) knots 0 0 0 0 1 1 1 1
  spline S80 degree 3 poles (-68.9614, 88.7847) (-68.4594, 88.6196) (-68.1637, 88.3446) (-68.1637, 88.042) knots 0 0 0 0 1 1 1 1
  spline S81 degree 3 poles (-69.759, 81.5235) (-70.9829, 81.7848) (-72.035, 82.0186) (-72.1037, 82.0324) knots 0 0 0 0 1 1 1 1
  spline S82 degree 2 poles (-66.0872, 66.1624) (-66.0734, 67.5238) (-66.0665, 68.6378) knots 0 0 0 1 1 1
  spline S83 degree 3 poles (-72.1037, 82.0324) (-72.2138, 82.0599) (-72.2275, 82.0117) (-72.2069, 81.4548) knots 0 0 0 0 1 1 1 1
  spline S84 degree 3 poles (-67.5655, 77.5767) (-67.6618, 77.5767) (-71.0104, 78.2711) (-71.0379, 78.2918) knots 0 0 0 0 1 1 1 1
  line L60 (-67.5587, 80.1277) -> (-67.5449, 81.0491)
  line L61 (-70.5566, 89.1491) -> (-70.3435, 89.1078)
  spline S85 degree 3 poles (-70.0272, 88.7434) (-69.814, 88.9359) (-69.4564, 88.9497) (-68.9614, 88.7847) knots 0 0 0 0 1 1 1 1
  spline S86 degree 3 poles (-68.425, 87.6226) (-68.7551, 87.4507) (-69.8346, 87.7395) (-70.0547, 88.0558) knots 0 0 0 0 1 1 1 1
  line L62 (-67.8543, 68.5071) -> (-66.0322, 69.0159)
  spline S87 degree 3 poles (-71.5055, 74.7919) (-71.4436, 75.0325) (-71.2236, 75.2388) (-71.0173, 75.2388) knots 0 0 0 0 1 1 1 1
  line L63 (-69.0576, 74.9019) -> (-68.8582, 74.7919)
  spline S88 degree 3 poles (-72.2206, 78.2918) (-72.2206, 77.611) (-72.2, 77.3566) (-72.1381, 77.336) knots 0 0 0 0 1 1 1 1
extrude "Extrusão10'" [suppressed] in component "Tampa"
component "Placa 9x7" placed x (1, 0, 0) y (0, 1, 0) z (0, 0, 1) at (0, 0, 0)
component "Suporte Placa (1)" placed x (1, 0, 0) y (0, 1, 0) z (0, 0, 1) at (0, 0, 0)
component "Tampa" placed x (1, 0, 0) y (0, 1, 0) z (0, 0, 1) at (0, 0, 0)
named bodies: "Placa 4x6"
